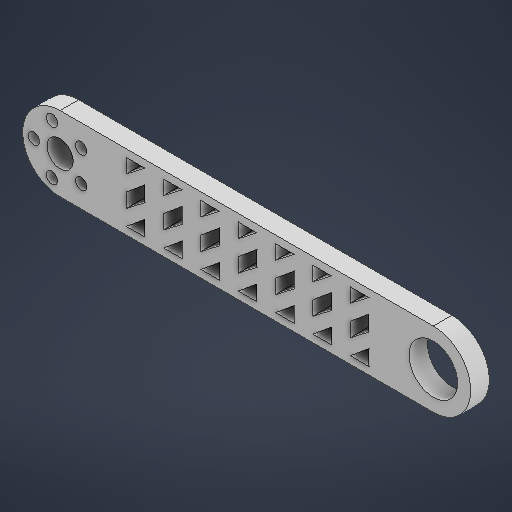
# Autodesk Inventor part: link1
Saved by Autodesk Inventor 2026.1 (Build 301233020, 233B)
## iProperties
Created: 2026-04-08
Part Number: link1
Material: Generic
Document SubType Name: Modeling
Designer: kadir
Density: 1 g/cm^3
Appearance: Default
Author: kadir
Autodesk Inventor part; units mm, degrees
ref_plane "YZ Plane" through (0, 0, 0) normal (1, 0, 0) x (0, 1, 0)
ref_plane "XZ Plane" through (0, 0, 0) normal (0, 1, 0) x (-1, 0, 0)
ref_plane "XY Plane" through (0, 0, 0) normal (0, 0, 1) x (1, 0, 0)
sketch "Sketch1" plane through (0, 0, 0) normal (0, 0, 1) x (1, 0, 0)
  circle A0 centre (0, 0) radius 10
  circle A1 centre (0, 0) radius 3.5
  circle A2 centre (-7, 0) radius 1.5
  circle A3 centre (-2.1631, -6.6574) radius 1.5
  circle A4 centre (5.6631, -4.1145) radius 1.5
  circle A5 centre (5.6631, 4.1145) radius 1.5
  circle A6 centre (-2.1631, 6.6574) radius 1.5
  circle A7 centre (100, 0) radius 6.5
  circle A8 centre (100, 0) radius 10
  line L0 (0, 10) -> (100, 10)
  line L1 (0, -10) -> (100, -10)
  line L2 (17.7568, 8) -> (22.7568, 8)
  line L3 (22.7568, 8) -> (22.7568, -8)
  line L4 (22.7568, -8) -> (17.7568, -8)
  line L5 (17.7568, -8) -> (17.7568, 8)
  line L6 (17.7568, 8) -> (22.7568, -8) construction
  line L7 (22.7568, 8) -> (17.7568, -8) construction
  line L8 (22.7568, 8) -> (17.7568, 4.1612)
  line L9 (22.7568, 0) -> (17.7568, -3.8388)
  line L10 (22.7568, 4.1612) -> (17.7568, 0)
  line L11 (17.7568, -8) -> (22.7568, -3.8388)
  line L12 (32.7568, -8) -> (27.7568, -8)
  line L13 (27.7568, -8) -> (32.7568, -3.8388)
  line L14 (32.7568, 0) -> (27.7568, -3.8388)
  line L15 (32.7568, 4.1612) -> (27.7568, 0)
  line L16 (27.7568, 8) -> (32.7568, 8)
  line L17 (32.7568, 8) -> (27.7568, 4.1612)
  line L18 (27.7568, -8) -> (27.7568, 8)
  line L19 (32.7568, 8) -> (32.7568, -8)
  line L20 (27.7568, 8) -> (32.7568, -8) construction
  line L21 (32.7568, 8) -> (27.7568, -8) construction
  line L22 (42.7568, -8) -> (37.7568, -8)
  line L23 (37.7568, -8) -> (42.7568, -3.8388)
  line L24 (42.7568, 0) -> (37.7568, -3.8388)
  line L25 (42.7568, 4.1612) -> (37.7568, 0)
  line L26 (37.7568, 8) -> (42.7568, 8)
  line L27 (42.7568, 8) -> (37.7568, 4.1612)
  line L28 (37.7568, -8) -> (37.7568, 8)
  line L29 (42.7568, 8) -> (42.7568, -8)
  line L30 (37.7568, 8) -> (42.7568, -8) construction
  line L31 (42.7568, 8) -> (37.7568, -8) construction
  line L32 (52.7568, -8) -> (47.7568, -8)
  line L33 (47.7568, -8) -> (52.7568, -3.8388)
  line L34 (52.7568, 0) -> (47.7568, -3.8388)
  line L35 (52.7568, 4.1612) -> (47.7568, 0)
  line L36 (47.7568, 8) -> (52.7568, 8)
  line L37 (52.7568, 8) -> (47.7568, 4.1612)
  line L38 (47.7568, -8) -> (47.7568, 8)
  line L39 (52.7568, 8) -> (52.7568, -8)
  line L40 (47.7568, 8) -> (52.7568, -8) construction
  line L41 (52.7568, 8) -> (47.7568, -8) construction
  line L42 (62.7568, -8) -> (57.7568, -8)
  line L43 (57.7568, -8) -> (62.7568, -3.8388)
  line L44 (62.7568, 0) -> (57.7568, -3.8388)
  line L45 (62.7568, 4.1612) -> (57.7568, 0)
  line L46 (57.7568, 8) -> (62.7568, 8)
  line L47 (62.7568, 8) -> (57.7568, 4.1612)
  line L48 (57.7568, -8) -> (57.7568, 8)
  line L49 (62.7568, 8) -> (62.7568, -8)
  line L50 (57.7568, 8) -> (62.7568, -8) construction
  line L51 (62.7568, 8) -> (57.7568, -8) construction
  line L52 (72.7568, -8) -> (67.7568, -8)
  line L53 (67.7568, -8) -> (72.7568, -3.8388)
  line L54 (72.7568, 0) -> (67.7568, -3.8388)
  line L55 (72.7568, 4.1612) -> (67.7568, 0)
  line L56 (67.7568, 8) -> (72.7568, 8)
  line L57 (72.7568, 8) -> (67.7568, 4.1612)
  line L58 (67.7568, -8) -> (67.7568, 8)
  line L59 (72.7568, 8) -> (72.7568, -8)
  line L60 (67.7568, 8) -> (72.7568, -8) construction
  line L61 (72.7568, 8) -> (67.7568, -8) construction
  line L62 (82.7568, -8) -> (77.7568, -8)
  line L63 (77.7568, -8) -> (82.7568, -3.8388)
  line L64 (82.7568, 0) -> (77.7568, -3.8388)
  line L65 (82.7568, 4.1612) -> (77.7568, 0)
  line L66 (77.7568, 8) -> (82.7568, 8)
  line L67 (82.7568, 8) -> (77.7568, 4.1612)
  line L68 (77.7568, -8) -> (77.7568, 8)
  line L69 (82.7568, 8) -> (82.7568, -8)
  line L70 (77.7568, 8) -> (82.7568, -8) construction
  line L71 (82.7568, 8) -> (77.7568, -8) construction
  point P0 (20.2568, 0)
  point P1 (30.2568, 0)
  point P2 (40.2568, 0)
  point P3 (50.2568, 0)
  point P4 (60.2568, 0)
  point P5 (70.2568, 0)
  point P6 (80.2568, 0)
  dimension "d0" = 20
  dimension "d1" = 7
  dimension "d2" = 3
  dimension "d5" = 360
  dimension "d7" = 13
  dimension "d8" = 20
  dimension "d9" = 100
  dimension "d10" = 5
  dimension "d11" = 16
  dimension "d14" = 10
  dimension "d25" = 7
  constraints: 144 end point, 28 point on line, 9 centre point, 4 midpoint, 4 parallel, 4 point on circle, 3 coincident, 2 horizontal, 2 horizontal alignment, 2 tangent, 1 perpendicular, 137 other
  measures "d0" diameter of A0
  measures "d1" diameter of A1
  measures "d2" diameter of A2
  measures "d7" diameter of A7
  measures "d8" diameter of A8
  measures "d9" distance of A7.centre point (0, 0)
  measures "d10" distance of L3.end L4.end
  measures "d11" distance of L2.end L3.end
  measures "d14" distance of L4.end L12.end
  measures "d25" distance of point (0, 0) A2.centre
extrude "Extrusion1" add sketch "Sketch1" along normal blind 5 contours A0 | A0 L0 A8 L1
extrude "Extrusion2" add sketch "Sketch1" along normal blind 5 contours L3 L10 L5 L8 | L3 L11 L5 L9 | L18 L14 L19 L13 | L18 L17 L19 L15 | L28 L24 L29 L23 | L28 L27 L29 L25 | L38 L34 L39 L33 | L38 L37 L39 L35 | L48 L44 L49 L43 | L48 L47 L49 L45 | L58 L54 L59 L53 | L58 L57 L59 L55 | L68 L64 L69 L63 | L68 L67 L69 L65
extrude "Extrusion3" add sketch "Sketch1" along normal blind 5 contours A8
body "Solid1"
